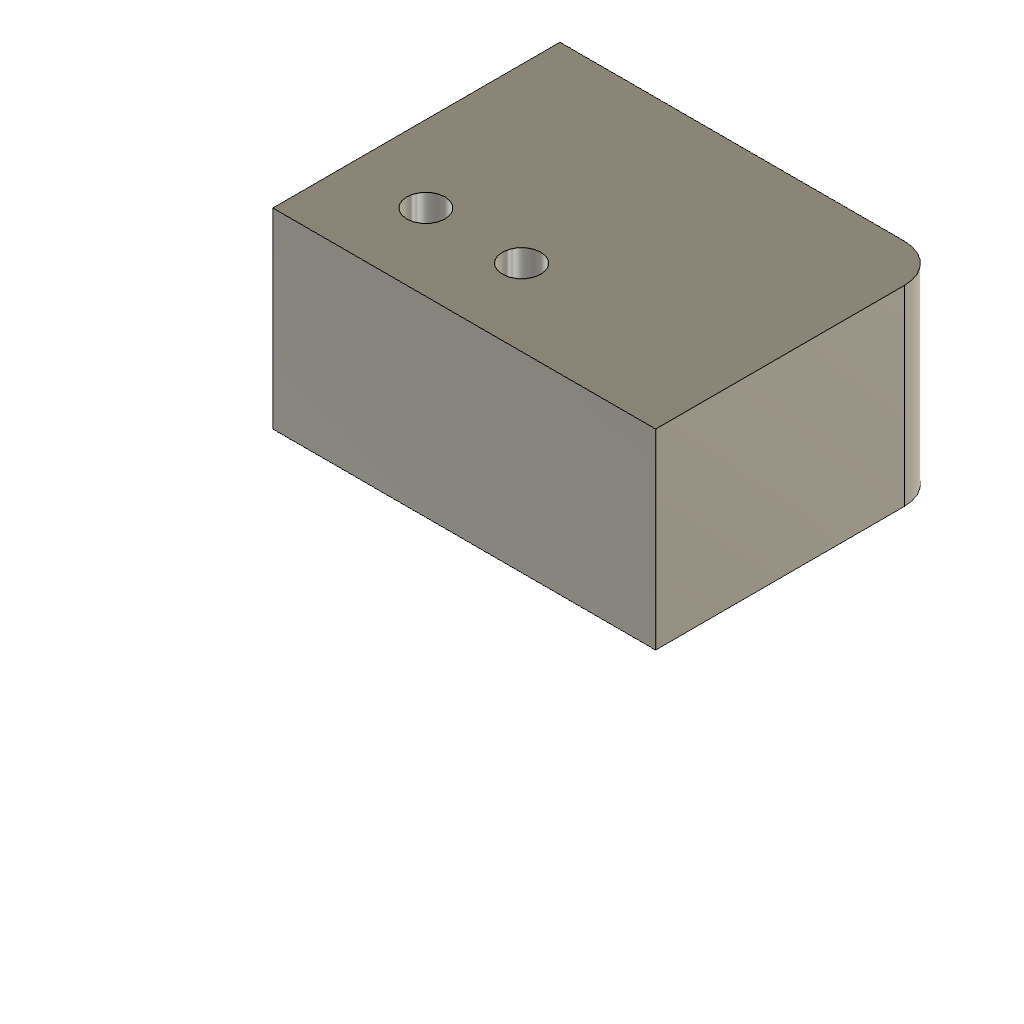
vendor_MultiPocketPart (Autodesk Fusion 360 design; units mm, degrees)
Autodesk Fusion 360 part; units mm, degrees
sketch "Base sketch" plane through (0, 0, 0) normal (0, 0, 1) x (1, 0, 0)
  line L0 (0, 0) -> (40, 0)
  line L1 (40, 0) -> (40, 30)
  line L2 (40, 30) -> (0, 30)
  line L3 (0, 30) -> (0, 0)
extrude "Base extrude" add sketch "Base sketch" along normal blind 20
sketch "Slot sketch" plane through (0, 0, 0) normal (0, 0, 1) x (1, 0, 0)
  line L0 (10, 19) -> (14, 19)
  arc A0 (14, 19) -> (14, 25) centre (14, 22) ccw
  line L1 (14, 25) -> (10, 25)
  arc A1 (10, 25) -> (10, 19) centre (10, 22) ccw
extrude "Slot pocket" cut sketch "Slot sketch" along normal blind 8
hole "Corner hole" at (8, 8, 20) direction (0, 0, -1) diameter 4 end through all
pattern_linear "Hole row" count 2 spacing 10 along (1, 0, 0) of "Corner hole"
fillet "Corner Round" radius 4 1 edges at (40, 30, 10)
ref_plane "WorkPlane1" through (21, 0, 0) normal (1, 0, 0) x (0, 1, 0)
mirror "Slot mirror" about plane through (21, 0, 0) normal (1, 0, 0) of "Slot pocket"
equation "height = 20.0 mm"
